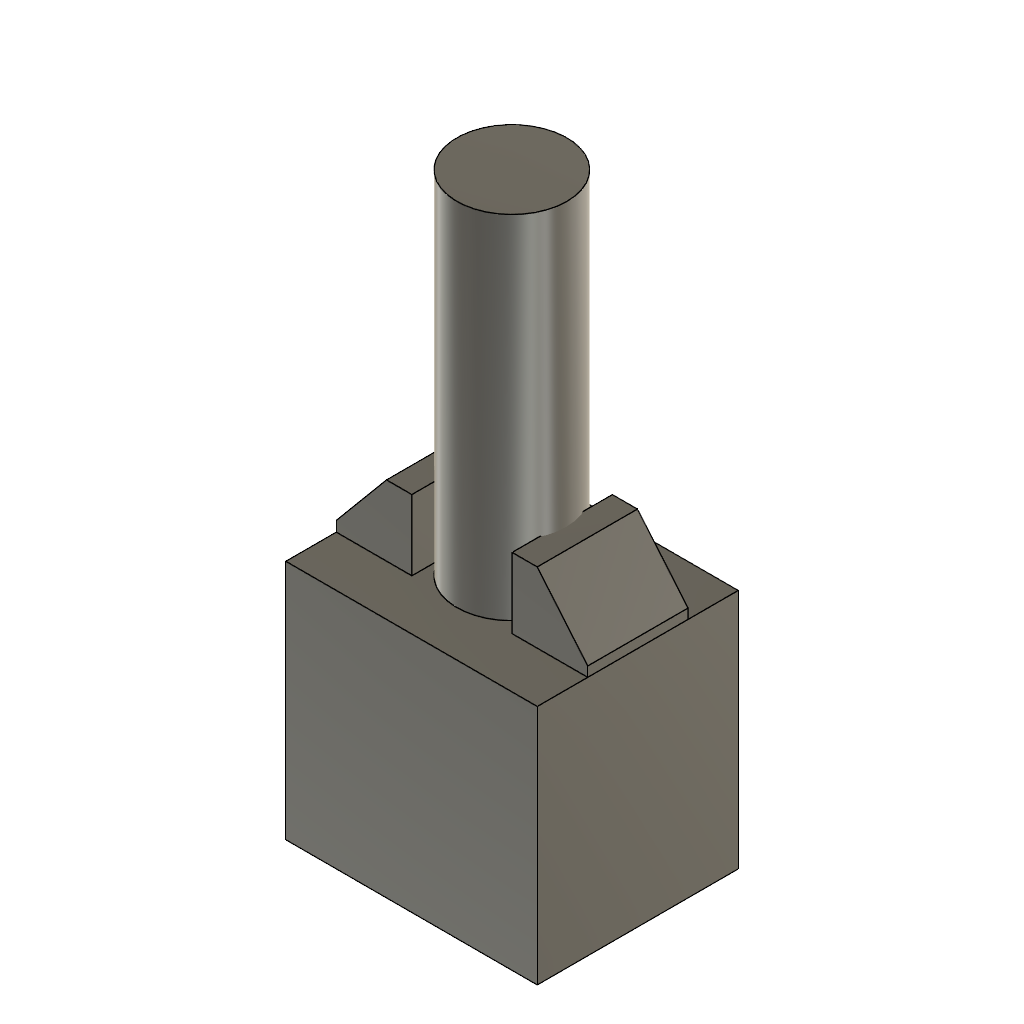
guitar_test (Autodesk Fusion 360 design; units mm, degrees)
part number: 2026-10-25-14-26-04-152
Autodesk Fusion 360 part; units mm, degrees
sketch "Sketch1" plane through (0, 0, 0) normal (0, 1, 0) x (1, 0, 0)
  line L0 (-125, 0) -> (125.2498, 0)
  line L1 (125.2498, 0) -> (125.2498, -240)
  line L2 (125.2498, -240) -> (-125, -240)
  line L3 (-125, -240) -> (-125, 0)
  constraint horizontal L0
  constraint vertical L1
  constraint horizontal L2
  constraint vertical L3
extrude "Extrude1" add sketch "Sketch1" along normal mid plane 200 makes body 1
sketch "Sketch3" plane through (0, 0, 240) normal (0, 0, 1) x (-1, 0, 0)
  line L0 (-125.2498, 100) -> (-125.2498, -100)
  line L1 (-125.2498, -100) -> (125, -100)
  line L2 (125, -100) -> (125, 100)
  line L3 (125, 100) -> (-125.2498, 100)
  circle A0 centre (0, 0) radius 54.8141
  constraint coincident A0.centre origin
extrude "Extrude3" add sketch "Sketch3" along normal blind 350 separate body contours A0 makes body 2
sketch "Sketch4" plane through (0, 0, 240) normal (0, 0, 1) x (-1, 0, 0)
  line L0 (-125.2498, 100) -> (-125.2498, -100)
  line L1 (-125.2498, -100) -> (125, -100)
  line L2 (125, -100) -> (125, 100)
  line L3 (125, 100) -> (-125.2498, 100)
  line L4 (-125.2498, 49.7799) -> (-50, 49.7799)
  line L5 (-50, 49.7799) -> (-50, -50)
  line L6 (-50, -50) -> (-125.2498, -50)
  line L7 (-125.2498, -50) -> (-125.2498, 49.7799)
  line L8 (49.7233, 49.7799) -> (125, 49.7799)
  line L9 (125, 49.7799) -> (125, -49.7953)
  line L10 (125, -49.7953) -> (49.7233, -49.7953)
  line L11 (49.7233, -49.7953) -> (49.7233, 49.7799)
  constraint horizontal L4
  constraint vertical L5
  constraint horizontal L6
  constraint vertical L7
  constraint coincident L0 L4.start
  constraint horizontal L8
  constraint vertical L9
  constraint horizontal L10
  constraint vertical L11
  constraint coincident L2 L9.end
extrude "Extrude4" add sketch "Sketch4" along normal blind 70 separate body contours L0 L4 L5 L6 L7 | L2 L8 L9 L10 L11 makes body 3 at (100.1665, -16.5199, 240) makes body 4 at (-74.8155, -16.5882, 240)
sketch "Sketch5" plane through (0, 50, 0) normal (0, 1, 0) x (-1, 0, 0)
  line L0 (-125.2498, 240) -> (-50, 240)
  line L1 (-50, 240) -> (-50, 310)
  line L2 (-50, 310) -> (-125.2498, 310)
  line L3 (-125.2498, 310) -> (-125.2498, 240)
  line L4 (-125.2498, 249.7927) -> (-75, 310)
  line L5 (-75, 310) -> (-125.2498, 310)
  line L6 (-125.2498, 249.7927) -> (-125.2498, 310)
  line L7 (0, 240) -> (0, 330)
  line L8 (125.2498, 249.7927) -> (125.2498, 310)
  line L9 (125.2498, 249.7927) -> (75, 310)
  line L10 (75, 310) -> (125.2498, 310)
  constraint coincident L3 L4.start
  constraint coincident L2 L4.end
  constraint coincident L2.end L3.start
  constraint vertical L7
  constraint symmetric L4.start L7 L8.start
  constraint symmetric L4.end L7 L9.end
  constraint symmetric L2.end L7 L8.end
extrude "Extrude5" cut sketch "Sketch5" against normal blind 200 contours L2 L3 L4 L5 L6 | L8 L9 L10 bodies 3 4
scale "Scale1" factor 2 about (125.2498, 100, 240) bodies 1 3 4 2
move_body "Move1" bodies 1 4 2 3 to x (1, 0, 0) y (0, 1, 0) z (0, 0, 1) at (126.6275, 0, 241.2936)
move_body "Move2" bodies 1 3 4 2 to x (1, 0, 0) y (0, 1, 0) z (0, 0, 1) at (0, 100, 0)
named bodies: "body_role-wood", "cyl_neck_role-dark", "loft_shoulder-l_role-wood", "loft_shoulder-r_role-wood"
